Autodesk Fusion 360 part; units mm, degrees
(part 5 of 9)
sketch "Switch trial spring 1 release 1 profile" plane through (0, -2.056, 23.4999) normal (0, -0.087156, 0.996195) x (1, 0, 0)
  line L0 (105.7897, 27.0995) -> (109.374, 27.0995)
  line L1 (109.374, 27.0995) -> (109.374, 27.6995)
  line L2 (109.374, 27.6995) -> (105.7897, 27.6995)
  line L3 (105.7897, 27.6995) -> (105.7897, 27.0995)
  dimension "d2652" = 105.7897
  dimension "d2653" = 27.0995
  dimension "d2654" = 3.5843
  dimension "d2655" = 0.6
  constraint horizontal L0
  constraint vertical L1
  constraint horizontal L2
  constraint vertical L3
  measures "d2652" horizontal distance of origin L0.start
  measures "d2653" vertical distance of origin L0.start
  measures "d2654" distance of L0.start L0.end
  measures "d2655" distance of L0.end L1.end
extrude "Switch trial spring 1 release 1" cut sketch "Switch trial spring 1 release 1 profile" against normal blind 10.7 bodies 5
sketch "Switch trial spring 1 release 2 profile" plane through (0, -2.056, 23.4999) normal (0, -0.087156, 0.996195) x (1, 0, 0)
  line L0 (105.7897, 29.6995) -> (109.374, 29.6995)
  line L1 (109.374, 29.6995) -> (109.374, 30.2995)
  line L2 (109.374, 30.2995) -> (105.7897, 30.2995)
  line L3 (105.7897, 30.2995) -> (105.7897, 29.6995)
  dimension "d2658" = 105.7897
  dimension "d2659" = 29.6995
  dimension "d2660" = 3.5843
  dimension "d2661" = 0.6
  constraint horizontal L0
  constraint vertical L1
  constraint horizontal L2
  constraint vertical L3
  measures "d2658" horizontal distance of origin L0.start
  measures "d2659" vertical distance of origin L0.start
  measures "d2660" distance of L0.start L0.end
  measures "d2661" distance of L0.end L1.end
extrude "Switch trial spring 1 release 2" cut sketch "Switch trial spring 1 release 2 profile" against normal blind 10.7 bodies 5
sketch "Switch trial spring 1 inner clearance profile" plane through (0, -1.6638, 19.017) normal (0, -0.087156, 0.996195) x (1, 0, 0)
  line L0 (106.6897, 27.6995) -> (109.374, 27.6995)
  line L1 (109.374, 27.6995) -> (109.374, 29.6995)
  line L2 (109.374, 29.6995) -> (106.6897, 29.6995)
  line L3 (106.6897, 29.6995) -> (106.6897, 27.6995)
  dimension "d2664" = 106.6897
  dimension "d2665" = 27.6995
  dimension "d2666" = 2.6843
  dimension "d2667" = 2
  constraint horizontal L0
  constraint vertical L1
  constraint horizontal L2
  constraint vertical L3
  measures "d2664" horizontal distance of origin L0.start
  measures "d2665" vertical distance of origin L0.start
  measures "d2666" distance of L0.start L0.end
  measures "d2667" distance of L0.end L1.end
extrude "Switch trial spring 1 inner clearance" cut sketch "Switch trial spring 1 inner clearance profile" against normal blind 6.2 bodies 5
sketch "Switch trial spring 1 hook profile" plane through (0, -1.2106, 13.8368) normal (0, -0.087156, 0.996195) x (1, 0, 0)
  line L0 (105.8897, 27.6995) -> (109.874, 27.6995)
  line L1 (109.874, 27.6995) -> (109.874, 29.6995)
  line L2 (109.874, 29.6995) -> (105.8897, 29.6995)
  line L3 (105.8897, 29.6995) -> (105.8897, 27.6995)
  dimension "d2670" = 105.8897
  dimension "d2671" = 27.6995
  dimension "d2672" = 3.9843
  dimension "d2673" = 2
  constraint horizontal L0
  constraint vertical L1
  constraint horizontal L2
  constraint vertical L3
  measures "d2670" horizontal distance of origin L0.start
  measures "d2671" vertical distance of origin L0.start
  measures "d2672" distance of L0.start L0.end
  measures "d2673" distance of L0.end L1.end
extrude "Switch trial spring 1 retaining hook" add sketch "Switch trial spring 1 hook profile" against normal blind 0.8 bodies 5
chamfer "Switch trial spring 1 45 degree lead-in" distance 0.35 angle 45 1 edges at (109.874, 27.4495, 15.5412) tangent chain off on bodies 5
sketch "Switch trial spring 2 release 1 profile" plane through (0, -2.056, 23.4999) normal (0, -0.087156, 0.996195) x (1, 0, 0)
  line L0 (120.8055, 27.0995) -> (124.3897, 27.0995)
  line L1 (124.3897, 27.0995) -> (124.3897, 27.6995)
  line L2 (124.3897, 27.6995) -> (120.8055, 27.6995)
  line L3 (120.8055, 27.6995) -> (120.8055, 27.0995)
  dimension "d2677" = 120.8055
  dimension "d2678" = 27.0995
  dimension "d2679" = 3.5843
  dimension "d2680" = 0.6
  constraint horizontal L0
  constraint vertical L1
  constraint horizontal L2
  constraint vertical L3
  measures "d2677" horizontal distance of origin L0.start
  measures "d2678" vertical distance of origin L0.start
  measures "d2679" distance of L0.start L0.end
  measures "d2680" distance of L0.end L1.end
extrude "Switch trial spring 2 release 1" cut sketch "Switch trial spring 2 release 1 profile" against normal blind 10.7 bodies 5
sketch "Switch trial spring 2 release 2 profile" plane through (0, -2.056, 23.4999) normal (0, -0.087156, 0.996195) x (1, 0, 0)
  line L0 (120.8055, 29.6995) -> (124.3897, 29.6995)
  line L1 (124.3897, 29.6995) -> (124.3897, 30.2995)
  line L2 (124.3897, 30.2995) -> (120.8055, 30.2995)
  line L3 (120.8055, 30.2995) -> (120.8055, 29.6995)
  dimension "d2683" = 120.8055
  dimension "d2684" = 29.6995
  dimension "d2685" = 3.5843
  dimension "d2686" = 0.6
  constraint horizontal L0
  constraint vertical L1
  constraint horizontal L2
  constraint vertical L3
  measures "d2683" horizontal distance of origin L0.start
  measures "d2684" vertical distance of origin L0.start
  measures "d2685" distance of L0.start L0.end
  measures "d2686" distance of L0.end L1.end
extrude "Switch trial spring 2 release 2" cut sketch "Switch trial spring 2 release 2 profile" against normal blind 10.7 bodies 5
sketch "Switch trial spring 2 inner clearance profile" plane through (0, -1.6638, 19.017) normal (0, -0.087156, 0.996195) x (1, 0, 0)
  line L0 (120.8055, 27.6995) -> (123.4897, 27.6995)
  line L1 (123.4897, 27.6995) -> (123.4897, 29.6995)
  line L2 (123.4897, 29.6995) -> (120.8055, 29.6995)
  line L3 (120.8055, 29.6995) -> (120.8055, 27.6995)
  dimension "d2689" = 120.8055
  dimension "d2690" = 27.6995
  dimension "d2691" = 2.6843
  dimension "d2692" = 2
  constraint horizontal L0
  constraint vertical L1
  constraint horizontal L2
  constraint vertical L3
  measures "d2689" horizontal distance of origin L0.start
  measures "d2690" vertical distance of origin L0.start
  measures "d2691" distance of L0.start L0.end
  measures "d2692" distance of L0.end L1.end
extrude "Switch trial spring 2 inner clearance" cut sketch "Switch trial spring 2 inner clearance profile" against normal blind 6.2 bodies 5
sketch "Switch trial spring 2 hook profile" plane through (0, -1.2106, 13.8368) normal (0, -0.087156, 0.996195) x (1, 0, 0)
  line L0 (120.3055, 27.6995) -> (124.2897, 27.6995)
  line L1 (124.2897, 27.6995) -> (124.2897, 29.6995)
  line L2 (124.2897, 29.6995) -> (120.3055, 29.6995)
  line L3 (120.3055, 29.6995) -> (120.3055, 27.6995)
  dimension "d2695" = 120.3055
  dimension "d2696" = 27.6995
  dimension "d2697" = 3.9843
  dimension "d2698" = 2
  constraint horizontal L0
  constraint vertical L1
  constraint horizontal L2
  constraint vertical L3
  measures "d2695" horizontal distance of origin L0.start
  measures "d2696" vertical distance of origin L0.start
  measures "d2697" distance of L0.start L0.end
  measures "d2698" distance of L0.end L1.end
extrude "Switch trial spring 2 retaining hook" add sketch "Switch trial spring 2 hook profile" against normal blind 0.8 bodies 5
chamfer "Switch trial spring 2 45 degree lead-in" distance 0.35 angle 45 1 edges at (120.3055, 27.4495, 15.5412) tangent chain off on bodies 5
sketch "Switch trial upper stop 1 profile" plane through (0, -1.6638, 19.017) normal (0, -0.087156, 0.996195) x (1, 0, 0)
  line L0 (111.5897, 28.9995) -> (112.5897, 28.9995)
  line L1 (112.5897, 28.9995) -> (112.5897, 33.7995)
  line L2 (112.5897, 33.7995) -> (111.5897, 33.7995)
  line L3 (111.5897, 33.7995) -> (111.5897, 28.9995)
  dimension "d2702" = 111.5897
  dimension "d2703" = 28.9995
  dimension "d2704" = 1
  dimension "d2705" = 4.8
  constraint horizontal L0
  constraint vertical L1
  constraint horizontal L2
  constraint vertical L3
  measures "d2702" horizontal distance of origin L0.start
  measures "d2703" vertical distance of origin L0.start
  measures "d2704" distance of L0.start L0.end
  measures "d2705" distance of L0.end L1.end
extrude "Switch trial upper stop 1" add sketch "Switch trial upper stop 1 profile" along normal blind 0.8 bodies 5
sketch "Switch trial upper stop 2 profile" plane through (0, -1.6638, 19.017) normal (0, -0.087156, 0.996195) x (1, 0, 0)
  line L0 (117.5897, 28.9995) -> (118.5897, 28.9995)
  line L1 (118.5897, 28.9995) -> (118.5897, 33.7995)
  line L2 (118.5897, 33.7995) -> (117.5897, 33.7995)
  line L3 (117.5897, 33.7995) -> (117.5897, 28.9995)
  dimension "d2708" = 117.5897
  dimension "d2709" = 28.9995
  dimension "d2710" = 1
  dimension "d2711" = 4.8
  constraint horizontal L0
  constraint vertical L1
  constraint horizontal L2
  constraint vertical L3
  measures "d2708" horizontal distance of origin L0.start
  measures "d2709" vertical distance of origin L0.start
  measures "d2710" distance of L0.start L0.end
  measures "d2711" distance of L0.end L1.end
extrude "Switch trial upper stop 2" add sketch "Switch trial upper stop 2 profile" along normal blind 0.8 bodies 5
sketch "Switch trial wire exit 1 profile" plane through (0, -1.5592, 17.8216) normal (0, -0.087156, 0.996195) x (1, 0, 0)
  line L0 (105.7897, 19.8995) -> (109.574, 19.8995)
  line L1 (109.574, 19.8995) -> (109.574, 27.6995)
  line L2 (109.574, 27.6995) -> (105.7897, 27.6995)
  line L3 (105.7897, 27.6995) -> (105.7897, 19.8995)
  dimension "d2714" = 105.7897
  dimension "d2715" = 19.8995
  dimension "d2716" = 3.7843
  dimension "d2717" = 7.8
  constraint horizontal L0
  constraint vertical L1
  constraint horizontal L2
  constraint vertical L3
  measures "d2714" horizontal distance of origin L0.start
  measures "d2715" vertical distance of origin L0.start
  measures "d2716" distance of L0.start L0.end
  measures "d2717" distance of L0.end L1.end
extrude "Switch trial wire exit 1" cut sketch "Switch trial wire exit 1 profile" against normal blind 5 bodies 5
sketch "Switch trial wire exit 2 profile" plane through (0, -1.5592, 17.8216) normal (0, -0.087156, 0.996195) x (1, 0, 0)
  line L0 (120.6055, 19.8995) -> (124.3897, 19.8995)
  line L1 (124.3897, 19.8995) -> (124.3897, 27.6995)
  line L2 (124.3897, 27.6995) -> (120.6055, 27.6995)
  line L3 (120.6055, 27.6995) -> (120.6055, 19.8995)
  dimension "d2720" = 120.6055
  dimension "d2721" = 19.8995
  dimension "d2722" = 3.7843
  dimension "d2723" = 7.8
  constraint horizontal L0
  constraint vertical L1
  constraint horizontal L2
  constraint vertical L3
  measures "d2720" horizontal distance of origin L0.start
  measures "d2721" vertical distance of origin L0.start
  measures "d2722" distance of L0.start L0.end
  measures "d2723" distance of L0.end L1.end
extrude "Switch trial wire exit 2" cut sketch "Switch trial wire exit 2 profile" against normal blind 5 bodies 5
sketch "Lid trial plate profile" plane through (0, 0, 0) normal (0, 0, 1) x (1, 0, 0)
  line L0 (104, 14.2032) -> (126, 14.2032)
  line L1 (126, 14.2032) -> (126, 36.2032)
  line L2 (126, 36.2032) -> (104, 36.2032)
  line L3 (104, 36.2032) -> (104, 14.2032)
  dimension "d2726" = 104
  dimension "d2727" = 14.2032
  dimension "d2728" = 22
  dimension "d2729" = 22
  constraint horizontal L0
  constraint vertical L1
  constraint horizontal L2
  constraint vertical L3
  measures "d2726" horizontal distance of origin L0.start
  measures "d2727" vertical distance of origin L0.start
  measures "d2728" distance of L0.start L0.end
  measures "d2729" distance of L0.end L1.end
extrude "Lid trial plate" add sketch "Lid trial plate profile" along normal blind 2 separate body makes body 6
sketch "Lid trial support 1 reinforced stem profile" plane through (0, 0, 2) normal (0, 0, 1) x (1, 0, 0)
  line L0 (111.3897, 20.0158) -> (113.7897, 20.0158)
  line L1 (113.7897, 20.0158) -> (113.7897, 25.0158)
  line L2 (113.7897, 25.0158) -> (111.3897, 25.0158)
  line L3 (111.3897, 25.0158) -> (111.3897, 20.0158)
  dimension "d2732" = 111.3897
  dimension "d2733" = 20.0158
  dimension "d2734" = 2.4
  dimension "d2735" = 5
  constraint horizontal L0
  constraint vertical L1
  constraint horizontal L2
  constraint vertical L3
  measures "d2732" horizontal distance of origin L0.start
  measures "d2733" vertical distance of origin L0.start
  measures "d2734" distance of L0.start L0.end
  measures "d2735" distance of L0.end L1.end
extrude "Lid trial support 1 reinforced stem" add sketch "Lid trial support 1 reinforced stem profile" along normal blind 11.7118 bodies 6
sketch "Lid trial support 1 profile" plane through (0, 0, 2) normal (0, 0, 1) x (1, 0, 0)
  line L0 (112.0897, 21.0158) -> (113.0897, 21.0158)
  line L1 (113.0897, 21.0158) -> (113.0897, 24.0158)
  line L2 (113.0897, 24.0158) -> (112.0897, 24.0158)
  line L3 (112.0897, 24.0158) -> (112.0897, 21.0158)
  dimension "d2738" = 112.0897
  dimension "d2739" = 21.0158
  dimension "d2740" = 1
  dimension "d2741" = 3
  constraint horizontal L0
  constraint vertical L1
  constraint horizontal L2
  constraint vertical L3
  measures "d2738" horizontal distance of origin L0.start
  measures "d2739" vertical distance of origin L0.start
  measures "d2740" distance of L0.start L0.end
  measures "d2741" distance of L0.end L1.end
extrude "Lid trial support 1" add sketch "Lid trial support 1 profile" along normal blind 14.2118 bodies 6
sketch "Lid trial support 1 cap profile" plane through (0, -1.1931, 13.6376) normal (0, -0.087156, 0.996195) x (1, 0, 0)
  line L0 (111.9897, 21.7995) -> (113.1897, 21.7995)
  line L1 (113.1897, 21.7995) -> (113.1897, 25.7995)
  line L2 (113.1897, 25.7995) -> (111.9897, 25.7995)
  line L3 (111.9897, 25.7995) -> (111.9897, 21.7995)
  dimension "d2744" = 111.9897
  dimension "d2745" = 21.7995
  dimension "d2746" = 1.2
  dimension "d2747" = 4
  constraint horizontal L0
  constraint vertical L1
  constraint horizontal L2
  constraint vertical L3
  measures "d2744" horizontal distance of origin L0.start
  measures "d2745" vertical distance of origin L0.start
  measures "d2746" distance of L0.start L0.end
  measures "d2747" distance of L0.end L1.end
extrude "Lid trial support 1 inclined cap" cut sketch "Lid trial support 1 cap profile" along normal blind 39.0612 bodies 6
sketch "Lid trial support 2 reinforced stem profile" plane through (0, 0, 2) normal (0, 0, 1) x (1, 0, 0)
  line L0 (116.3897, 20.0158) -> (118.7897, 20.0158)
  line L1 (118.7897, 20.0158) -> (118.7897, 25.0158)
  line L2 (118.7897, 25.0158) -> (116.3897, 25.0158)
  line L3 (116.3897, 25.0158) -> (116.3897, 20.0158)
  dimension "d2750" = 116.3897
  dimension "d2751" = 20.0158
  dimension "d2752" = 2.4
  dimension "d2753" = 5
  constraint horizontal L0
  constraint vertical L1
  constraint horizontal L2
  constraint vertical L3
  measures "d2750" horizontal distance of origin L0.start
  measures "d2751" vertical distance of origin L0.start
  measures "d2752" distance of L0.start L0.end
  measures "d2753" distance of L0.end L1.end
extrude "Lid trial support 2 reinforced stem" add sketch "Lid trial support 2 reinforced stem profile" along normal blind 11.7118 bodies 6
sketch "Lid trial support 2 profile" plane through (0, 0, 2) normal (0, 0, 1) x (1, 0, 0)
  line L0 (117.0897, 21.0158) -> (118.0897, 21.0158)
  line L1 (118.0897, 21.0158) -> (118.0897, 24.0158)
  line L2 (118.0897, 24.0158) -> (117.0897, 24.0158)
  line L3 (117.0897, 24.0158) -> (117.0897, 21.0158)
  dimension "d2756" = 117.0897
  dimension "d2757" = 21.0158
  dimension "d2758" = 1
  dimension "d2759" = 3
  constraint horizontal L0
  constraint vertical L1
  constraint horizontal L2
  constraint vertical L3
  measures "d2756" horizontal distance of origin L0.start
  measures "d2757" vertical distance of origin L0.start
  measures "d2758" distance of L0.start L0.end
  measures "d2759" distance of L0.end L1.end
extrude "Lid trial support 2" add sketch "Lid trial support 2 profile" along normal blind 14.2118 bodies 6
sketch "Lid trial support 2 cap profile" plane through (0, -1.1931, 13.6376) normal (0, -0.087156, 0.996195) x (1, 0, 0)
  line L0 (116.9897, 21.7995) -> (118.1897, 21.7995)
  line L1 (118.1897, 21.7995) -> (118.1897, 25.7995)
  line L2 (118.1897, 25.7995) -> (116.9897, 25.7995)
  line L3 (116.9897, 25.7995) -> (116.9897, 21.7995)
  dimension "d2762" = 116.9897
  dimension "d2763" = 21.7995
  dimension "d2764" = 1.2
  dimension "d2765" = 4
  constraint horizontal L0
  constraint vertical L1
  constraint horizontal L2
  constraint vertical L3
  measures "d2762" horizontal distance of origin L0.start
  measures "d2763" vertical distance of origin L0.start
  measures "d2764" distance of L0.start L0.end
  measures "d2765" distance of L0.end L1.end
extrude "Lid trial support 2 inclined cap" cut sketch "Lid trial support 2 cap profile" along normal blind 39.0612 bodies 6
sketch "Compact V2 plate profile" plane through (0, -2.2739, 25.9904) normal (0, -0.087156, 0.996195) x (1, 0, 0)
  line L0 (134, 15.4972) -> (156, 15.4972)
  line L1 (156, 15.4972) -> (156, 37.4972)
  line L2 (156, 37.4972) -> (134, 37.4972)
  line L3 (134, 37.4972) -> (134, 15.4972)
  dimension "d2773" = 134
  dimension "d2774" = 15.4972
  dimension "d2775" = 22
  dimension "d2776" = 22
  constraint horizontal L0
  constraint vertical L1
  constraint horizontal L2
  constraint vertical L3
  measures "d2773" horizontal distance of origin L0.start
  measures "d2774" vertical distance of origin L0.start
  measures "d2775" distance of L0.start L0.end
  measures "d2776" distance of L0.end L1.end
extrude "Compact V2 plate" add sketch "Compact V2 plate profile" against normal blind 1.5 separate body makes body 7
sketch "Compact V2 switch seat profile" plane through (0, -2.2739, 25.9904) normal (0, -0.087156, 0.996195) x (1, 0, 0)
  line L0 (137.95, 19.4472) -> (152.05, 19.4472)
  line L1 (152.05, 19.4472) -> (152.05, 33.5472)
  line L2 (152.05, 33.5472) -> (137.95, 33.5472)
  line L3 (137.95, 33.5472) -> (137.95, 19.4472)
  dimension "d2779" = 137.95
  dimension "d2780" = 19.4472
  dimension "d2781" = 14.1
  dimension "d2782" = 14.1
  constraint horizontal L0
  constraint vertical L1
  constraint horizontal L2
  constraint vertical L3
  measures "d2779" horizontal distance of origin L0.start
  measures "d2780" vertical distance of origin L0.start
  measures "d2781" distance of L0.start L0.end
  measures "d2782" distance of L0.end L1.end
extrude "Compact V2 switch seat" cut sketch "Compact V2 switch seat profile" against normal blind 1.6 bodies 7
sketch "Compact V2 rigid receiver profile" plane through (0, -2.1431, 24.4961) normal (0, -0.087156, 0.996195) x (1, 0, 0)
  line L0 (135.8, 17.6972) -> (154.2, 17.6972)
  line L1 (154.2, 17.6972) -> (154.2, 35.2972)
  line L2 (154.2, 35.2972) -> (135.8, 35.2972)
  line L3 (135.8, 35.2972) -> (135.8, 17.6972)
  dimension "d2785" = 135.8
  dimension "d2786" = 17.6972
  dimension "d2787" = 18.4
  dimension "d2788" = 17.6
  constraint horizontal L0
  constraint vertical L1
  constraint horizontal L2
  constraint vertical L3
  measures "d2785" horizontal distance of origin L0.start
  measures "d2786" vertical distance of origin L0.start
  measures "d2787" distance of L0.start L0.end
  measures "d2788" distance of L0.end L1.end
extrude "Compact V2 continuous receiver" add sketch "Compact V2 rigid receiver profile" against normal blind 10.7 bodies 7
sketch "Compact V2 switch body profile" plane through (0, -2.1431, 24.4961) normal (0, -0.087156, 0.996195) x (1, 0, 0)
  line L0 (137, 18.4972) -> (153, 18.4972)
  line L1 (153, 18.4972) -> (153, 34.4972)
  line L2 (153, 34.4972) -> (137, 34.4972)
  line L3 (137, 34.4972) -> (137, 18.4972)
  dimension "d2791" = 137
  dimension "d2792" = 18.4972
  dimension "d2793" = 16
  dimension "d2794" = 16
  constraint horizontal L0
  constraint vertical L1
  constraint horizontal L2
  constraint vertical L3
  measures "d2791" horizontal distance of origin L0.start
  measures "d2792" vertical distance of origin L0.start
  measures "d2793" distance of L0.start L0.end
  measures "d2794" distance of L0.end L1.end
extrude "Compact V2 switch clearance" cut sketch "Compact V2 switch body profile" against normal blind 5.5 bodies 7
sketch "Compact V2 registered pocket profile" plane through (0, -1.6638, 19.017) normal (0, -0.087156, 0.996195) x (1, 0, 0)
  line L0 (139.374, 19.925) -> (150.8055, 19.925)
  line L1 (150.8055, 19.925) -> (150.8055, 30.0741)
  line L2 (150.8055, 30.0741) -> (139.374, 30.0741)
  line L3 (139.374, 30.0741) -> (139.374, 19.925)
  dimension "d2797" = 139.374
  dimension "d2798" = 19.925
  dimension "d2799" = 11.4315
  dimension "d2800" = 10.1491
  constraint horizontal L0
  constraint vertical L1
  constraint horizontal L2
  constraint vertical L3
  measures "d2797" horizontal distance of origin L0.start
  measures "d2798" vertical distance of origin L0.start
  measures "d2799" distance of L0.start L0.end
  measures "d2800" distance of L0.end L1.end
extrude "Compact V2 open-bottom pocket" cut sketch "Compact V2 registered pocket profile" against normal blind 5.3 bodies 7
sketch "Compact V2 stop -1 profile" plane through (0, -1.6638, 19.017) normal (0, -0.087156, 0.996195) x (1, 0, 0)
  line L0 (141.1, 29.0972) -> (142.9, 29.0972)
  line L1 (142.9, 29.0972) -> (142.9, 35.2972)
  line L2 (142.9, 35.2972) -> (141.1, 35.2972)
  line L3 (141.1, 35.2972) -> (141.1, 29.0972)
  dimension "d2803" = 141.1
  dimension "d2804" = 29.0972
  dimension "d2805" = 1.8
  dimension "d2806" = 6.2
  constraint horizontal L0
  constraint vertical L1
  constraint horizontal L2
  constraint vertical L3
  measures "d2803" horizontal distance of origin L0.start
  measures "d2804" vertical distance of origin L0.start
  measures "d2805" distance of L0.start L0.end
  measures "d2806" distance of L0.end L1.end
extrude "Compact V2 widened stop -1" add sketch "Compact V2 stop -1 profile" along normal blind 0.8 bodies 7
sketch "Compact V2 guide web -1 profile" plane through (0, -1.2106, 13.8368) normal (0, -0.087156, 0.996195) x (1, 0, 0)
  line L0 (135.8, 26.1472) -> (140.2, 26.1472)
  line L1 (140.2, 26.1472) -> (140.2, 26.8472)
  line L2 (140.2, 26.8472) -> (135.8, 26.8472)
  line L3 (135.8, 26.8472) -> (135.8, 26.1472)
  dimension "d2809" = 135.8
  dimension "d2810" = 26.1472
  dimension "d2811" = 4.4
  dimension "d2812" = 0.7
  constraint horizontal L0
  constraint vertical L1
  constraint horizontal L2
  constraint vertical L3
  measures "d2809" horizontal distance of origin L0.start
  measures "d2810" vertical distance of origin L0.start
  measures "d2811" distance of L0.start L0.end
  measures "d2812" distance of L0.end L1.end
extrude "Compact V2 guide web -1" add sketch "Compact V2 guide web -1 profile" along normal blind 3 bodies 7
sketch "Compact V2 rounded guide -1 profile" plane through (0, -1.2106, 13.8368) normal (0, -0.087156, 0.996195) x (1, 0, 0)
  circle A0 centre (140.2, 26.4972) radius 0.75
  dimension "d2815" = 140.2
  dimension "d2817" = 1.5
  measures "d2815" horizontal distance of origin A0.centre
  measures "d2817" diameter of A0
extrude "Compact V2 rounded guide -1" add sketch "Compact V2 rounded guide -1 profile" along normal blind 3 bodies 7
sketch "Compact V2 stop 1 profile" plane through (0, -1.6638, 19.017) normal (0, -0.087156, 0.996195) x (1, 0, 0)
  line L0 (147.1, 29.0972) -> (148.9, 29.0972)
  line L1 (148.9, 29.0972) -> (148.9, 35.2972)
  line L2 (148.9, 35.2972) -> (147.1, 35.2972)
  line L3 (147.1, 35.2972) -> (147.1, 29.0972)
  dimension "d2820" = 147.1
  dimension "d2821" = 29.0972
  dimension "d2822" = 1.8
  dimension "d2823" = 6.2
  constraint horizontal L0
  constraint vertical L1
  constraint horizontal L2
  constraint vertical L3
  measures "d2820" horizontal distance of origin L0.start
  measures "d2821" vertical distance of origin L0.start
  measures "d2822" distance of L0.start L0.end
  measures "d2823" distance of L0.end L1.end
extrude "Compact V2 widened stop 1" add sketch "Compact V2 stop 1 profile" along normal blind 0.8 bodies 7
sketch "Compact V2 guide web 1 profile" plane through (0, -1.2106, 13.8368) normal (0, -0.087156, 0.996195) x (1, 0, 0)
  line L0 (149.8, 26.1472) -> (154.2, 26.1472)
  line L1 (154.2, 26.1472) -> (154.2, 26.8472)
  line L2 (154.2, 26.8472) -> (149.8, 26.8472)
  line L3 (149.8, 26.8472) -> (149.8, 26.1472)
  dimension "d2826" = 149.8
  dimension "d2827" = 26.1472
  dimension "d2828" = 4.4
  dimension "d2829" = 0.7
  constraint horizontal L0
  constraint vertical L1
  constraint horizontal L2
  constraint vertical L3
  measures "d2826" horizontal distance of origin L0.start
  measures "d2827" vertical distance of origin L0.start
  measures "d2828" distance of L0.start L0.end
  measures "d2829" distance of L0.end L1.end
extrude "Compact V2 guide web 1" add sketch "Compact V2 guide web 1 profile" along normal blind 3 bodies 7
sketch "Compact V2 rounded guide 1 profile" plane through (0, -1.2106, 13.8368) normal (0, -0.087156, 0.996195) x (1, 0, 0)
  circle A0 centre (149.8, 26.4972) radius 0.75
  dimension "d2832" = 149.8
  dimension "d2834" = 1.5
  measures "d2832" horizontal distance of origin A0.centre
  measures "d2834" diameter of A0
extrude "Compact V2 rounded guide 1" add sketch "Compact V2 rounded guide 1 profile" along normal blind 3 bodies 7
ref_plane "WorkPlane35" through (135, 0, 0) normal (1, 0, 0) x (0, 1, 0)
sketch "Compact V2 X wire 1 profile" plane through (135, 0, 0) normal (1, 0, 0) x (0, 0, -1)
  circle A0 centre (-17.0628, 22.596) radius 0.75
  dimension "d2839" = 17.0628
  dimension "d2840" = 22.596
  dimension "d2841" = 1.5
  measures "d2839" horizontal distance of origin A0.centre
  measures "d2840" vertical distance of origin A0.centre
  measures "d2841" diameter of A0
extrude "Compact V2 X wire 1 through channel" cut sketch "Compact V2 X wire 1 profile" along normal blind 20 bodies 7
sketch "Compact V2 X wire 2 profile" plane through (135, 0, 0) normal (1, 0, 0) x (0, 0, -1)
  circle A0 centre (-16.8701, 20.003) radius 0.75
  dimension "d2844" = 16.8701
  dimension "d2845" = 20.003
  dimension "d2846" = 1.5
  measures "d2844" horizontal distance of origin A0.centre
  measures "d2845" vertical distance of origin A0.centre
  measures "d2846" diameter of A0
extrude "Compact V2 X wire 2 through channel" cut sketch "Compact V2 X wire 2 profile" along normal blind 20 bodies 7
sketch "Compact V2 X wire 3 profile" plane through (135, 0, 0) normal (1, 0, 0) x (0, 0, -1)
  circle A0 centre (-19.9612, 21.8295) radius 0.75
  dimension "d2849" = 19.9612
  dimension "d2850" = 21.8295
  dimension "d2851" = 1.5
  measures "d2849" horizontal distance of origin A0.centre
  measures "d2850" vertical distance of origin A0.centre
  measures "d2851" diameter of A0
extrude "Compact V2 X wire 3 through channel" cut sketch "Compact V2 X wire 3 profile" along normal blind 20 bodies 7
ref_plane "WorkPlane36" through (12.125, 0, 0) normal (0, 0.996195, 0.087156) x (1, 0, 0)
ref_plane "WorkPlane37" through (12.125, 36.3583, 3.1809) normal (0, 0.996195, 0.087156) x (1, 0, 0)
sketch "Compact V2 Y wire profile" plane through (0, 36.3583, 3.1809) normal (0, 0.996195, 0.087156) x (1, 0, 0)
  circle A0 centre (149.1902, -17.9827) radius 0.75
  dimension "d2858" = 149.1902
  dimension "d2859" = 17.9827
  dimension "d2860" = 1.5
  measures "d2858" horizontal distance of origin A0.centre
  measures "d2859" vertical distance of origin A0.centre
  measures "d2860" diameter of A0
extrude "Compact V2 Y wire through channel" cut sketch "Compact V2 Y wire profile" against normal blind 20 bodies 7
other "Base Mesh Feature1"
hidden bodies 1 2 3 4 5
equation "caseWidth = 80 mm" comment "Exterior width"
equation "caseLength = 115 mm" comment "Horizontal front-to-rear footprint"
equation "caseTilt = 5 deg" comment "Rear-up face angle; provisional"
equation "frontHeight = 29 mm" comment "Draft height, to be checked against electronics"
equation "rearHeight = frontHeight + caseLength * tan(caseTilt)" comment "Rear height"
equation "shellWall = 2.4 mm" comment "Draft shell thickness"
equation "bottomThickness = 2 mm" comment "Service cover thickness"
equation "carrierThickness = 1.5 mm" comment "Local switch clip seating thickness"
equation "carrierClearance = 0.4 mm" comment "Draft carrier clearance"
equation "carrierRim = 7 mm" comment "Carrier frame width"
equation "keycapSize = 18 mm" comment "Confirmed square keycap size"
equation "layoutGap = ( caseWidth - 3 * keycapSize ) / 4" comment "Equal visible horizontal gaps"
equation "keyPitch = keycapSize + layoutGap" comment "Equal row and column pitch"
equation "switchOpening = 14.1 mm" comment "Draft opening; coupon verification required"
equation "upperSwitchOpening = 16.2 mm" comment "Draft outer trim clearance"
equation "displayWidth = 34.5 mm" comment "User-supplied window width"
equation "displayHeight = 18.5 mm" comment "User-supplied window height"
equation "encoderKnobDiameter = 20 mm" comment "Placeholder; actual knob diameter required"
equation "encoderHole = 7 mm" comment "User-supplied provisional opening; verify bushing"
equation "ledWidth = 67 mm" comment "User-supplied strip width"
equation "ledHeight = 10 mm" comment "Initial diffuser opening height"
equation "diffuserClearance = 0.2 mm" comment "Per-edge draft fit clearance"
equation "diffuserFlange = 1.5 mm" comment "Retaining flange extension per side"
equation "diffuserFlangeThickness = 1 mm" comment "Retaining flange thickness"
equation "faceLength = caseLength / cos(caseTilt)" comment "Length measured in the inclined face"
equation "faceOriginV = frontHeight * sin(caseTilt)" comment "Inclined sketch origin correction"
equation "controlHeight = max(displayHeight; encoderKnobDiameter)" comment "Visible controls row height"
equation "contentLength = 2 * keycapSize + 3 * layoutGap + controlHeight + ledHeight" comment "Visible layout stack"
equation "verticalMargin = ( faceLength - contentLength ) / 2" comment "Balanced front and rear margins"
equation "keyRowOne = verticalMargin + keycapSize / 2" comment "Front key row center"
equation "keyRowTwo = keyRowOne + keyPitch" comment "Rear key row center"
equation "controlCenter = keyRowTwo + keycapSize / 2 + layoutGap + controlHeight / 2" comment "Display and encoder center"
equation "ledCenter = controlCenter + controlHeight / 2 + layoutGap + ledHeight / 2" comment "LED opening center"
equation "encoderCenterX = ( layoutGap + displayWidth + caseWidth ) / 2" comment "Centered in the area right of the display"
equation "d39 = -( ( 0 ) * ( 0 mm ) + ( -1 ) * ( bottomThickness ) )"
equation "d40 = ( ( 1 ) * ( caseLength ) + ( 0 ) * ( bottomThickness ) ) - ( ( 1 ) * ( 0 mm ) + ( 0 ) * ( bottomThickness ) )"
equation "d41 = -( ( ( 0 ) * ( caseLength ) + ( -1 ) * ( rearHeight ) ) - ( ( 0 ) * ( caseLength ) + ( -1 ) * ( bottomThickness ) ) )"
equation "d42 = ( ( 0 ) * ( 0 mm ) + ( -1 ) * ( bottomThickness ) ) - ( ( 0 ) * ( 0 mm ) + ( -1 ) * ( frontHeight ) )"
equation "d43 = caseWidth"
equation "d45 = shellWall"
equation "d46 = caseTilt"
equation "d48 = frontHeight * cos(caseTilt)"
equation "d50 = -( shellWall + carrierClearance )"
equation "d52 = shellWall + carrierClearance"
equation "d53 = ( ( shellWall + carrierClearance ) / cos(caseTilt) - ( shellWall + carrierClearance ) * tan(caseTilt) ) + faceOriginV"
equation "d54 = ( ( shellWall + carrierClearance ) + ( caseWidth - 2 * ( shellWall + carrierClearance ) ) ) - ( shellWall + carrierClearance )"
equation "d55 = carrierFaceLength"
equation "d56 = -( carrierThickness )"
equation "d58 = ( caseWidth - carrierBayWidth ) / 2"
equation "d59 = ( keyRowTwo + keycapSize / 2 + layoutGap / 2 ) + faceOriginV"
equation "d60 = carrierBayWidth"
equation "d61 = faceLength - ( shellWall + carrierClearance ) / cos(caseTilt) - ( shellWall + carrierClearance + carrierThickness ) * tan(caseTilt) - carrierRim - ( keyRowTwo + keycapSize / 2 + layoutGap / 2 )"
equation "d62 = -( carrierThickness + 1 mm )"
equation "d64 = ( layoutGap + keycapSize / 2 + 0 * keyPitch ) - switchOpening / 2"
equation "d65 = ( ( keyRowOne ) - switchOpening / 2 ) + faceOriginV"
equation "d66 = ( ( ( layoutGap + keycapSize / 2 + 0 * keyPitch ) - switchOpening / 2 ) + ( switchOpening ) ) - ( ( layoutGap + keycapSize / 2 + 0 * keyPitch ) - switchOpening / 2 )"
equation "d67 = ( ( ( ( keyRowOne ) - switchOpening / 2 ) + faceOriginV ) + ( switchOpening ) ) - ( ( ( keyRowOne ) - switchOpening / 2 ) + faceOriginV )"
equation "d68 = -( carrierThickness + 1 mm )"
equation "d70 = ( layoutGap + keycapSize / 2 + 0 * keyPitch ) - upperSwitchOpening / 2"
equation "d71 = ( ( keyRowOne ) - upperSwitchOpening / 2 ) + faceOriginV"
equation "d72 = ( ( ( layoutGap + keycapSize / 2 + 0 * keyPitch ) - upperSwitchOpening / 2 ) + ( upperSwitchOpening ) ) - ( ( layoutGap + keycapSize / 2 + 0 * keyPitch ) - upperSwitchOpening / 2 )"
equation "d73 = ( ( ( ( keyRowOne ) - upperSwitchOpening / 2 ) + faceOriginV ) + ( upperSwitchOpening ) ) - ( ( ( keyRowOne ) - upperSwitchOpening / 2 ) + faceOriginV )"
equation "d74 = -( shellWall + 1 mm )"
equation "d76 = ( layoutGap + keycapSize / 2 + 1 * keyPitch ) - switchOpening / 2"
equation "d77 = ( ( keyRowOne ) - switchOpening / 2 ) + faceOriginV"
equation "d78 = ( ( ( layoutGap + keycapSize / 2 + 1 * keyPitch ) - switchOpening / 2 ) + ( switchOpening ) ) - ( ( layoutGap + keycapSize / 2 + 1 * keyPitch ) - switchOpening / 2 )"
equation "d79 = ( ( ( ( keyRowOne ) - switchOpening / 2 ) + faceOriginV ) + ( switchOpening ) ) - ( ( ( keyRowOne ) - switchOpening / 2 ) + faceOriginV )"
equation "d80 = -( carrierThickness + 1 mm )"
equation "d82 = ( layoutGap + keycapSize / 2 + 1 * keyPitch ) - upperSwitchOpening / 2"
equation "d83 = ( ( keyRowOne ) - upperSwitchOpening / 2 ) + faceOriginV"
equation "d84 = ( ( ( layoutGap + keycapSize / 2 + 1 * keyPitch ) - upperSwitchOpening / 2 ) + ( upperSwitchOpening ) ) - ( ( layoutGap + keycapSize / 2 + 1 * keyPitch ) - upperSwitchOpening / 2 )"
equation "d85 = ( ( ( ( keyRowOne ) - upperSwitchOpening / 2 ) + faceOriginV ) + ( upperSwitchOpening ) ) - ( ( ( keyRowOne ) - upperSwitchOpening / 2 ) + faceOriginV )"
equation "d86 = -( shellWall + 1 mm )"
equation "d88 = ( layoutGap + keycapSize / 2 + 2 * keyPitch ) - switchOpening / 2"
equation "d89 = ( ( keyRowOne ) - switchOpening / 2 ) + faceOriginV"
equation "d90 = ( ( ( layoutGap + keycapSize / 2 + 2 * keyPitch ) - switchOpening / 2 ) + ( switchOpening ) ) - ( ( layoutGap + keycapSize / 2 + 2 * keyPitch ) - switchOpening / 2 )"
equation "d91 = ( ( ( ( keyRowOne ) - switchOpening / 2 ) + faceOriginV ) + ( switchOpening ) ) - ( ( ( keyRowOne ) - switchOpening / 2 ) + faceOriginV )"
equation "d92 = -( carrierThickness + 1 mm )"
equation "d94 = ( layoutGap + keycapSize / 2 + 2 * keyPitch ) - upperSwitchOpening / 2"
equation "d95 = ( ( keyRowOne ) - upperSwitchOpening / 2 ) + faceOriginV"
equation "d96 = ( ( ( layoutGap + keycapSize / 2 + 2 * keyPitch ) - upperSwitchOpening / 2 ) + ( upperSwitchOpening ) ) - ( ( layoutGap + keycapSize / 2 + 2 * keyPitch ) - upperSwitchOpening / 2 )"
equation "d97 = ( ( ( ( keyRowOne ) - upperSwitchOpening / 2 ) + faceOriginV ) + ( upperSwitchOpening ) ) - ( ( ( keyRowOne ) - upperSwitchOpening / 2 ) + faceOriginV )"
equation "d98 = -( shellWall + 1 mm )"
equation "d100 = ( layoutGap + keycapSize / 2 + 0 * keyPitch ) - switchOpening / 2"
equation "d101 = ( ( keyRowTwo ) - switchOpening / 2 ) + faceOriginV"
equation "d102 = ( ( ( layoutGap + keycapSize / 2 + 0 * keyPitch ) - switchOpening / 2 ) + ( switchOpening ) ) - ( ( layoutGap + keycapSize / 2 + 0 * keyPitch ) - switchOpening / 2 )"
equation "d103 = ( ( ( ( keyRowTwo ) - switchOpening / 2 ) + faceOriginV ) + ( switchOpening ) ) - ( ( ( keyRowTwo ) - switchOpening / 2 ) + faceOriginV )"
equation "d104 = -( carrierThickness + 1 mm )"
equation "d106 = ( layoutGap + keycapSize / 2 + 0 * keyPitch ) - upperSwitchOpening / 2"
equation "d107 = ( ( keyRowTwo ) - upperSwitchOpening / 2 ) + faceOriginV"
equation "d108 = ( ( ( layoutGap + keycapSize / 2 + 0 * keyPitch ) - upperSwitchOpening / 2 ) + ( upperSwitchOpening ) ) - ( ( layoutGap + keycapSize / 2 + 0 * keyPitch ) - upperSwitchOpening / 2 )"
equation "d109 = ( ( ( ( keyRowTwo ) - upperSwitchOpening / 2 ) + faceOriginV ) + ( upperSwitchOpening ) ) - ( ( ( keyRowTwo ) - upperSwitchOpening / 2 ) + faceOriginV )"
equation "d110 = -( shellWall + 1 mm )"
equation "d112 = ( layoutGap + keycapSize / 2 + 1 * keyPitch ) - switchOpening / 2"
equation "d113 = ( ( keyRowTwo ) - switchOpening / 2 ) + faceOriginV"
equation "d114 = ( ( ( layoutGap + keycapSize / 2 + 1 * keyPitch ) - switchOpening / 2 ) + ( switchOpening ) ) - ( ( layoutGap + keycapSize / 2 + 1 * keyPitch ) - switchOpening / 2 )"
equation "d115 = ( ( ( ( keyRowTwo ) - switchOpening / 2 ) + faceOriginV ) + ( switchOpening ) ) - ( ( ( keyRowTwo ) - switchOpening / 2 ) + faceOriginV )"
equation "d116 = -( carrierThickness + 1 mm )"
equation "d118 = ( layoutGap + keycapSize / 2 + 1 * keyPitch ) - upperSwitchOpening / 2"
equation "d119 = ( ( keyRowTwo ) - upperSwitchOpening / 2 ) + faceOriginV"
equation "d120 = ( ( ( layoutGap + keycapSize / 2 + 1 * keyPitch ) - upperSwitchOpening / 2 ) + ( upperSwitchOpening ) ) - ( ( layoutGap + keycapSize / 2 + 1 * keyPitch ) - upperSwitchOpening / 2 )"
equation "d121 = ( ( ( ( keyRowTwo ) - upperSwitchOpening / 2 ) + faceOriginV ) + ( upperSwitchOpening ) ) - ( ( ( keyRowTwo ) - upperSwitchOpening / 2 ) + faceOriginV )"
equation "d122 = -( shellWall + 1 mm )"
equation "d124 = ( layoutGap + keycapSize / 2 + 2 * keyPitch ) - switchOpening / 2"
equation "d125 = ( ( keyRowTwo ) - switchOpening / 2 ) + faceOriginV"
equation "d126 = ( ( ( layoutGap + keycapSize / 2 + 2 * keyPitch ) - switchOpening / 2 ) + ( switchOpening ) ) - ( ( layoutGap + keycapSize / 2 + 2 * keyPitch ) - switchOpening / 2 )"
equation "d127 = ( ( ( ( keyRowTwo ) - switchOpening / 2 ) + faceOriginV ) + ( switchOpening ) ) - ( ( ( keyRowTwo ) - switchOpening / 2 ) + faceOriginV )"
equation "d128 = -( carrierThickness + 1 mm )"
equation "d130 = ( layoutGap + keycapSize / 2 + 2 * keyPitch ) - upperSwitchOpening / 2"
equation "d131 = ( ( keyRowTwo ) - upperSwitchOpening / 2 ) + faceOriginV"
equation "d132 = ( ( ( layoutGap + keycapSize / 2 + 2 * keyPitch ) - upperSwitchOpening / 2 ) + ( upperSwitchOpening ) ) - ( ( layoutGap + keycapSize / 2 + 2 * keyPitch ) - upperSwitchOpening / 2 )"
equation "d133 = ( ( ( ( keyRowTwo ) - upperSwitchOpening / 2 ) + faceOriginV ) + ( upperSwitchOpening ) ) - ( ( ( keyRowTwo ) - upperSwitchOpening / 2 ) + faceOriginV )"
equation "d134 = -( shellWall + 1 mm )"
equation "d136 = ( caseWidth - ledWidth ) / 2"
equation "d137 = ( ledCenter - ledHeight / 2 ) + faceOriginV"
equation "d138 = ( ( ( caseWidth - ledWidth ) / 2 ) + ( ledWidth ) ) - ( ( caseWidth - ledWidth ) / 2 )"
equation "d139 = ( ( ( ledCenter - ledHeight / 2 ) + faceOriginV ) + ( ledHeight ) ) - ( ( ledCenter - ledHeight / 2 ) + faceOriginV )"
equation "d140 = -( shellWall + 1 mm )"
equation "d142 = layoutGap"
equation "d143 = ( controlCenter - displayHeight / 2 ) + faceOriginV"
equation "d144 = ( ( layoutGap ) + ( displayWidth ) ) - ( layoutGap )"
equation "d145 = ( ( ( controlCenter - displayHeight / 2 ) + faceOriginV ) + ( displayHeight ) ) - ( ( controlCenter - displayHeight / 2 ) + faceOriginV )"
equation "d146 = -( shellWall + 1 mm )"
equation "d148 = encoderCenterX"
equation "d149 = controlCenter + faceOriginV"
equation "d150 = encoderHole"
equation "d151 = -( shellWall + 1 mm )"
equation "d153 = ( ( 0 mm ) + ( caseWidth ) ) - ( 0 mm )"
equation "d154 = ( ( 0 mm ) + ( caseLength ) ) - ( 0 mm )"
equation "d155 = bottomThickness"
equation "d157 = ( caseWidth - ledWidth ) / 2 + diffuserClearance"
equation "d158 = ( ledCenter - ledHeight / 2 + diffuserClearance ) + faceOriginV"
equation "d159 = ( ( ( caseWidth - ledWidth ) / 2 + diffuserClearance ) + ( ledWidth - 2 * diffuserClearance ) ) - ( ( caseWidth - ledWidth ) / 2 + diffuserClearance )"
equation "d160 = ( ( ( ledCenter - ledHeight / 2 + diffuserClearance ) + faceOriginV ) + ( ledHeight - 2 * diffuserClearance ) ) - ( ( ledCenter - ledHeight / 2 + diffuserClearance ) + faceOriginV )"
equation "d161 = -( shellWall )"
equation "d163 = -shellWall"
equation "d165 = ( caseWidth - ledWidth ) / 2 + diffuserClearance - diffuserFlange"
equation "d166 = ( ledCenter - ledHeight / 2 + diffuserClearance - diffuserFlange ) + faceOriginV"
equation "d167 = ( ( ( caseWidth - ledWidth ) / 2 + diffuserClearance - diffuserFlange ) + ( ledWidth - 2 * diffuserClearance + 2 * diffuserFlange ) ) - ( ( caseWidth - ledWidth ) / 2 + diffuserClearance - diffuserFlange )"
equation "d168 = ( ( ( ledCenter - ledHeight / 2 + diffuserClearance - diffuserFlange ) + faceOriginV ) + ( ledHeight - 2 * diffuserClearance + 2 * diffuserFlange ) ) - ( ( ledCenter - ledHeight / 2 + diffuserClearance - diffuserFlange ) + faceOriginV )"
equation "d169 = -( diffuserFlangeThickness )"
equation "carrierFaceLength = faceLength - 2 * ( shellWall + carrierClearance ) / cos(caseTilt) - carrierThickness * tan(caseTilt)" comment "Carrier rear clearance"
equation "d172 = layoutGap + 0 * keyPitch"
equation "d173 = ( keyRowOne - keycapSize / 2 ) + faceOriginV"
equation "d174 = ( ( layoutGap + 0 * keyPitch ) + ( keycapSize ) ) - ( layoutGap + 0 * keyPitch )"
equation "d175 = ( ( ( keyRowOne - keycapSize / 2 ) + faceOriginV ) + ( keycapSize ) ) - ( ( keyRowOne - keycapSize / 2 ) + faceOriginV )"
equation "d176 = layoutGap + 1 * keyPitch"
equation "d177 = ( keyRowOne - keycapSize / 2 ) + faceOriginV"
equation "d178 = ( ( layoutGap + 1 * keyPitch ) + ( keycapSize ) ) - ( layoutGap + 1 * keyPitch )"
equation "d179 = ( ( ( keyRowOne - keycapSize / 2 ) + faceOriginV ) + ( keycapSize ) ) - ( ( keyRowOne - keycapSize / 2 ) + faceOriginV )"
equation "d180 = layoutGap + 2 * keyPitch"
equation "d181 = ( keyRowOne - keycapSize / 2 ) + faceOriginV"
equation "d182 = ( ( layoutGap + 2 * keyPitch ) + ( keycapSize ) ) - ( layoutGap + 2 * keyPitch )"
equation "d183 = ( ( ( keyRowOne - keycapSize / 2 ) + faceOriginV ) + ( keycapSize ) ) - ( ( keyRowOne - keycapSize / 2 ) + faceOriginV )"
equation "d184 = layoutGap + 0 * keyPitch"
equation "d185 = ( keyRowTwo - keycapSize / 2 ) + faceOriginV"
equation "d186 = ( ( layoutGap + 0 * keyPitch ) + ( keycapSize ) ) - ( layoutGap + 0 * keyPitch )"
equation "d187 = ( ( ( keyRowTwo - keycapSize / 2 ) + faceOriginV ) + ( keycapSize ) ) - ( ( keyRowTwo - keycapSize / 2 ) + faceOriginV )"
equation "d188 = layoutGap + 1 * keyPitch"
equation "d189 = ( keyRowTwo - keycapSize / 2 ) + faceOriginV"
equation "d190 = ( ( layoutGap + 1 * keyPitch ) + ( keycapSize ) ) - ( layoutGap + 1 * keyPitch )"
equation "d191 = ( ( ( keyRowTwo - keycapSize / 2 ) + faceOriginV ) + ( keycapSize ) ) - ( ( keyRowTwo - keycapSize / 2 ) + faceOriginV )"
equation "d192 = layoutGap + 2 * keyPitch"
equation "d193 = ( keyRowTwo - keycapSize / 2 ) + faceOriginV"
equation "d194 = ( ( layoutGap + 2 * keyPitch ) + ( keycapSize ) ) - ( layoutGap + 2 * keyPitch )"
equation "d195 = ( ( ( keyRowTwo - keycapSize / 2 ) + faceOriginV ) + ( keycapSize ) ) - ( ( keyRowTwo - keycapSize / 2 ) + faceOriginV )"
equation "d196 = encoderCenterX"
equation "d197 = controlCenter + faceOriginV"
equation "d198 = encoderKnobDiameter"
equation "flangePocketClearance = 0.2 mm" comment "Carrier pocket clearance"
equation "d200 = ( caseWidth - ledWidth ) / 2 + diffuserClearance - diffuserFlange - flangePocketClearance"
equation "d201 = ( ledCenter - ledHeight / 2 + diffuserClearance - diffuserFlange - flangePocketClearance ) + faceOriginV"
equation "d202 = ( ( ( caseWidth - ledWidth ) / 2 + diffuserClearance - diffuserFlange - flangePocketClearance ) + ( ledWidth - 2 * diffuserClearance + 2 * diffuserFlange + 2 * flangePocketClearance ) ) - ( ( caseWidth - ledWidth ) / 2 + diffuserClearance - diffuserFlange - flangePocketClearance )"
equation "d203 = ( ( ( ledCenter - ledHeight / 2 + diffuserClearance - diffuserFlange - flangePocketClearance ) + faceOriginV ) + ( ledHeight - 2 * diffuserClearance + 2 * diffuserFlange + 2 * flangePocketClearance ) ) - ( ( ledCenter - ledHeight / 2 + diffuserClearance - diffuserFlange - flangePocketClearance ) + faceOriginV )"
equation "d204 = -( diffuserFlangeThickness - carrierClearance + flangePocketClearance )"
equation "carrierBayWidth = min(caseWidth - 2 * ( shellWall + carrierClearance + carrierRim ); ledWidth - 2 * diffuserClearance + 2 * diffuserFlange - 2 mm)" comment "Electronics opening preserving diffuser support rails"
equation "mountSideX = 12 mm" comment "Carrier fastener center from side"
equation "mountFrontV = 10.5 mm" comment "Front fastener center in face coordinates"
equation "mountRearV = faceLength - 9.64 mm" comment "Rear fastener center in face coordinates"
equation "mountBossDiameter = 7 mm" comment "Wall-connected M2 boss diameter"
equation "insertLength = 4 mm" comment "Confirmed M2 insert length"
equation "insertOuterDiameter = 3.5 mm" comment "Confirmed M2 insert outer diameter"
equation "insertPilotDiameter = 3.2 mm" comment "Provisional PLA pilot; test coupon required"
equation "insertPilotDepth = insertLength + 0.5 mm" comment "Blind insert pocket depth"
equation "carrierBossDepth = 7.4 mm" comment "Shell boss bottom below exterior face"
equation "carrierPadDepth = 10 mm" comment "Carrier pad bottom below exterior face"
equation "mountPocketClearance = 0.3 mm + ( carrierBossDepth - shellWall - carrierClearance ) * tan(caseTilt)" comment "Per-side carrier boss clearance"
equation "mountPadWidth = 12 mm" comment "Carrier mounting pad width"
equation "mountPadLength = 9.4 mm" comment "Carrier mounting pad length"
equation "m2Clearance = 2.3 mm" comment "Draft M2 screw clearance"
equation "bottomBossHeight = 6 mm" comment "Independent cover boss height above lid"
equation "carrierRibWidth = 2 mm" comment "Switch-field reinforcing rib width"
equation "carrierRibDepth = 3 mm" comment "Reinforcement below switch plate"
equation "d224 = -carrierBossDepth"
equation "d226 = -( carrierBossDepth + carrierClearance )"
equation "d228 = bottomThickness"
equation "d230 = mountSideX"
equation "d231 = ( mountFrontV ) + faceOriginV"
equation "d232 = mountBossDiameter"
equation "d233 = -( carrierBossDepth )"
equation "d235 = mountSideX"
equation "d236 = ( mountFrontV ) + faceOriginV"
equation "d237 = insertPilotDiameter"
equation "d238 = insertPilotDepth"
equation "d240 = ( mountSideX ) - mountPadWidth / 2"
equation "d241 = ( ( mountFrontV ) - mountPadLength / 2 ) + faceOriginV"
equation "d242 = ( ( shellWall + carrierClearance ) + ( mountPadWidth ) ) - ( shellWall + carrierClearance )"
equation "d243 = ( ( ( ( mountFrontV ) - mountPadLength / 2 ) + faceOriginV ) + ( mountPadLength ) ) - ( ( ( mountFrontV ) - mountPadLength / 2 ) + faceOriginV )"
equation "d244 = -( carrierPadDepth - shellWall - carrierClearance )"
equation "d246 = mountSideX"
equation "d247 = ( mountFrontV ) + faceOriginV"
equation "d248 = mountBossDiameter + 2 * mountPocketClearance"
equation "d249 = carrierBossDepth + carrierClearance"
equation "d251 = mountSideX"
equation "d252 = ( mountFrontV ) + faceOriginV"
equation "d253 = m2Clearance"
equation "d254 = -( carrierPadDepth )"
equation "d258 = bottomBossDiameter"
equation "d259 = bottomBossHeight"
equation "d263 = insertPilotDiameter"
equation "d264 = insertPilotDepth"
equation "d268 = m2Clearance"
equation "d269 = -( bottomThickness + 0.5 mm )"
equation "d271 = caseWidth - mountSideX"
equation "d272 = ( mountFrontV ) + faceOriginV"
equation "d273 = mountBossDiameter"
equation "d274 = -( carrierBossDepth )"
equation "d276 = caseWidth - mountSideX"
equation "d277 = ( mountFrontV ) + faceOriginV"
equation "d278 = insertPilotDiameter"
equation "d279 = insertPilotDepth"
equation "d281 = ( caseWidth - mountSideX ) - mountPadWidth / 2"
equation "d282 = ( ( mountFrontV ) - mountPadLength / 2 ) + faceOriginV"
equation "d283 = ( ( caseWidth - shellWall - carrierClearance - mountPadWidth ) + ( mountPadWidth ) ) - ( caseWidth - shellWall - carrierClearance - mountPadWidth )"
equation "d284 = ( ( ( ( mountFrontV ) - mountPadLength / 2 ) + faceOriginV ) + ( mountPadLength ) ) - ( ( ( mountFrontV ) - mountPadLength / 2 ) + faceOriginV )"
equation "d285 = -( carrierPadDepth - shellWall - carrierClearance )"
equation "d287 = caseWidth - mountSideX"
equation "d288 = ( mountFrontV ) + faceOriginV"
equation "d289 = mountBossDiameter + 2 * mountPocketClearance"
equation "d290 = carrierBossDepth + carrierClearance"
equation "d292 = caseWidth - mountSideX"
equation "d293 = ( mountFrontV ) + faceOriginV"
equation "d294 = m2Clearance"
equation "d295 = -( carrierPadDepth )"
equation "d297 = caseWidth - 20 mm"
equation "d299 = bottomBossDiameter"
equation "d300 = bottomBossHeight"
equation "d302 = caseWidth - 20 mm"
equation "d304 = insertPilotDiameter"
equation "d305 = insertPilotDepth"
equation "d307 = caseWidth - 20 mm"
equation "d309 = m2Clearance"
equation "d310 = -( bottomThickness + 0.5 mm )"
equation "d312 = mountSideX"
equation "d313 = ( mountRearV ) + faceOriginV"
equation "d314 = mountBossDiameter"
equation "d315 = -( carrierBossDepth )"
equation "d317 = mountSideX"
equation "d318 = ( mountRearV ) + faceOriginV"
equation "d319 = insertPilotDiameter"
equation "d320 = insertPilotDepth"
equation "d322 = ( mountSideX ) - mountPadWidth / 2"
equation "d323 = ( ( mountRearV ) - mountPadLength / 2 ) + faceOriginV"
equation "d324 = ( ( shellWall + carrierClearance ) + ( mountPadWidth ) ) - ( shellWall + carrierClearance )"
equation "d325 = ( ( ( ( mountRearV ) - mountPadLength / 2 ) + faceOriginV ) + ( mountPadLength ) ) - ( ( ( mountRearV ) - mountPadLength / 2 ) + faceOriginV )"
equation "d326 = -( carrierPadDepth - shellWall - carrierClearance )"
equation "d328 = mountSideX"